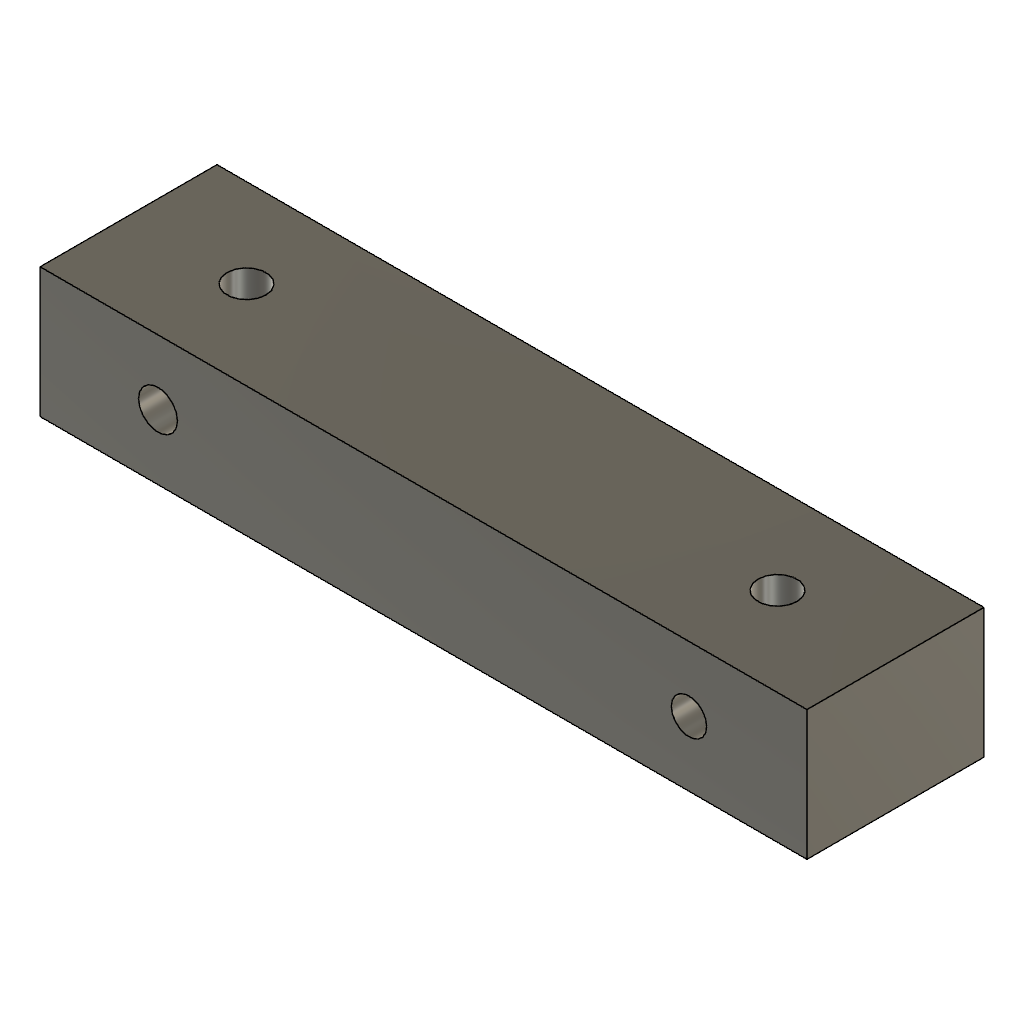
ecotwin_final (Autodesk Fusion 360 archive; units mm, degrees)
design "loadcell"
part number: 2026-10-23-00-33-52-910
Autodesk Fusion 360 part; units mm, degrees
sketch "Sketch1" plane through (0, 0, 0) normal (0, 0, 1) x (1, 0, 0)
  line L0 (0, 0) -> (130, 0)
  line L1 (130, 0) -> (130, 30)
  line L2 (130, 30) -> (0, 30)
  line L3 (0, 30) -> (0, 0)
  dimension "d1" = 130
  dimension "d2" = 30
  constraint horizontal L0
  constraint vertical L1
  constraint horizontal L2
  constraint vertical L3
  constraint coincident L0.start L3.end
  measures "d1" distance of L0.start L0.end
  measures "d2" distance of L0.start L2.end
extrude "Extrude1" add sketch "Sketch1" along normal blind 22
sketch "Sketch2" plane through (0, 0, 22) normal (0, 0, 1) x (-1, 0, 0)
  line L0 (0, -30) -> (0, 0)
  line L1 (0, 0) -> (-130, 0)
  line L2 (-130, 0) -> (-130, -30)
  line L3 (-130, -30) -> (0, -30)
  circle A0 centre (-110, -15) radius 3.3
  circle A1 centre (-20, -15) radius 3.3
  dimension "d7" = 6.6
  dimension "d8" = 6.6
  dimension "d11" = 15
  dimension "d12" = 20
  dimension "d13" = 20
  dimension "d15" = 15
  measures "d7" diameter of A0
  measures "d8" diameter of A1
  measures "d11" distance of L1 A1.centre
  measures "d12" distance of L0 A1.centre
  measures "d13" distance of L2 A0.centre
  measures "d15" distance of L1 A0.centre
sketch "Sketch3" plane through (0, 30, 0) normal (0, 1, 0) x (-1, 0, 0)
  line L0 (-130, 0) -> (0, 0)
  line L1 (0, 0) -> (0, 22)
  line L2 (0, 22) -> (-130, 22)
  line L3 (-130, 22) -> (-130, 0)
  circle A0 centre (-20, 11) radius 3.3
  circle A1 centre (-110, 11) radius 3
  dimension "d17" = 6.6
  dimension "d18" = 6
  dimension "d19" = 20
  dimension "d20" = 11
  dimension "d21" = 11
  dimension "d22" = 20
  measures "d17" diameter of A0
  measures "d18" diameter of A1
  measures "d19" distance of L1 A0.centre
  measures "d20" distance of L0 A0.centre
  measures "d21" distance of L0 A1.centre
  measures "d22" distance of L3 A1.centre
extrude "Extrude2" cut sketch "Sketch2" against normal blind 3 contours A0 | A1
extrude "Extrude3" cut sketch "Sketch3" against normal blind 3 contours A0 | A1
extrude "Extrude4" cut 2 faces at (19.1719, 16.8039, 19) (110.8064, 14.2518, 19) along direction (0, 0, -1) through all
extrude "Extrude5" cut 2 faces at (19.2059, 27, 11.9121) (110.7442, 27, 11.5311) along direction (0, -1, 0) through all

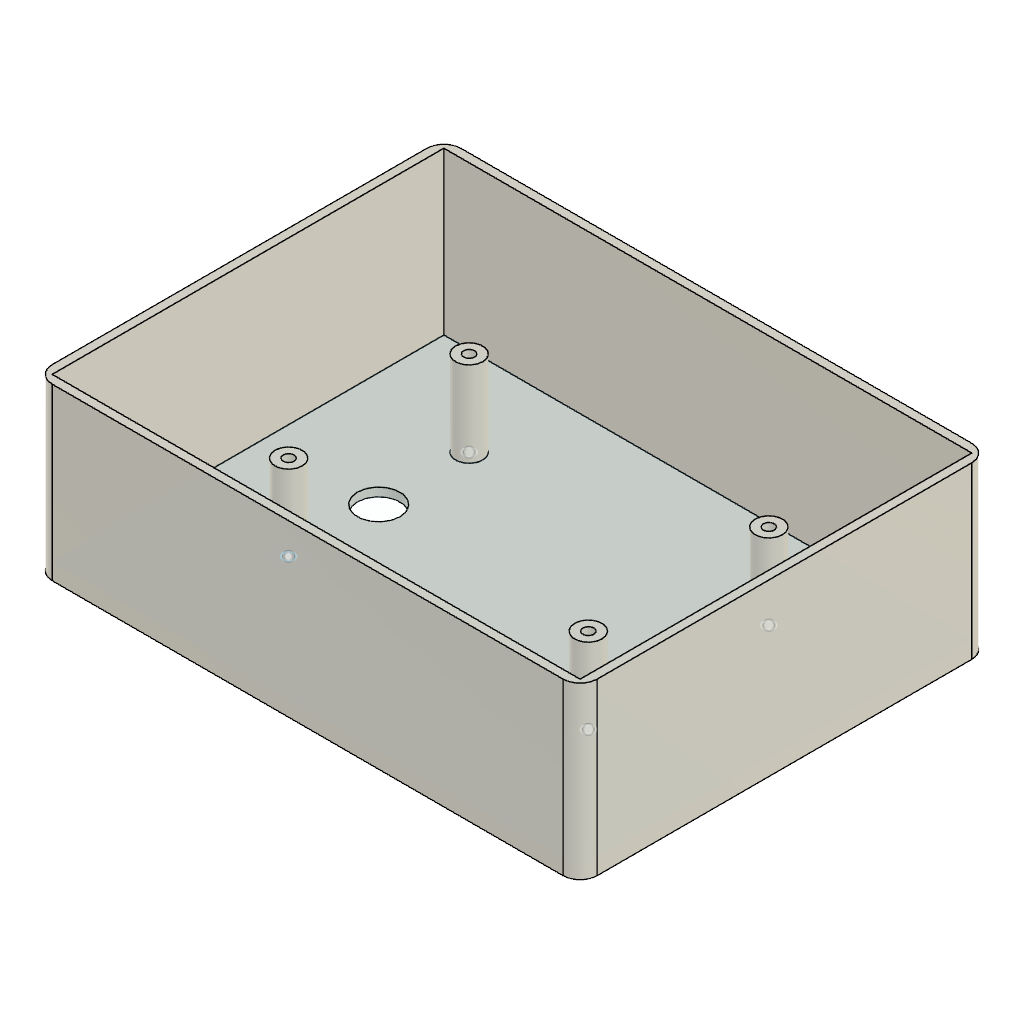
design "brain pod"
part number: 2026-10-24-10-44-46-187
Autodesk Fusion 360 part; units mm, degrees
sketch "Sketch1" plane through (0, 0, 0) normal (0, 0, 1) x (1, 0, 0)
  line L0 (0, 0) -> (160, 0)
  line L1 (160, 0) -> (160, 120)
  line L2 (160, 120) -> (0, 120)
  line L3 (0, 120) -> (0, 0)
  dimension "d1" = 160
  dimension "d2" = 120
  constraint horizontal L0
  constraint vertical L1
  constraint horizontal L2
  constraint vertical L3
  constraint coincident L0.start L3.end
  measures "d1" distance of L0.start L0.end
  measures "d2" distance of L0.start L2.end
extrude "Extrude1" add sketch "Sketch1" along normal blind 50
shell "Shell1" thickness 2.5 removed faces 1 at (53.3333, 80, 50)
fillet "Fillet1" radius 5 4 edges at (0, 0, 25) (160, 120, 25) (160, 0, 25) (0, 120, 25)
sketch "Sketch2" plane through (0, 0, 2.5) normal (0, 0, 1) x (-1, 0, 0)
  line L0 (-2.5, -117.5) -> (-2.5, -2.5)
  line L1 (-2.5, -2.5) -> (-157.5, -2.5)
  line L2 (-157.5, -2.5) -> (-157.5, -117.5)
  line L3 (-157.5, -117.5) -> (-2.5, -117.5)
  circle A0 centre (-36, -91.4107) radius 4
  circle A1 centre (-124, -91.4107) radius 4
  circle A2 centre (-36, -38.4107) radius 4
  circle A3 centre (-124, -38.4107) radius 4
  line L4 (-80, -120) -> (-80, -60)
  line L5 (-0.0841, -64.9107) -> (-80.0841, -64.9107)
  dimension "d8" = 8
  dimension "d9" = 8
  dimension "d10" = 8
  dimension "d11" = 8
  dimension "d12" = 60
  dimension "d13" = 80
  dimension "d14" = 44
  dimension "d15" = 44
  dimension "d16" = 44
  dimension "d17" = 44
  dimension "d18" = 26.5
  dimension "d19" = 26.5
  dimension "d20" = 26.5
  dimension "d21" = 26.5
  constraint perpendicular L3 L4
  constraint perpendicular L0 L5
  measures "d8" diameter of A0
  measures "d9" diameter of A1
  measures "d10" diameter of A2
  measures "d11" diameter of A3
  measures "d12" distance of L4.start L4.end
  measures "d13" distance of L5.start L5.end
  measures "d14" distance of A0.centre L4
  measures "d15" distance of A1.centre L4
  measures "d16" distance of A2.centre L4
  measures "d17" distance of A3.centre L4
  measures "d18" distance of A0.centre L5
  measures "d19" distance of A1.centre L5
  measures "d20" distance of A2.centre L5
  measures "d21" distance of A3.centre L5
extrude "Extrude2" add sketch "Sketch2" along normal blind 25 contours A0 | A1 | A2 | A3
sketch "Sketch3" plane through (0, 0, 2.5) normal (0, 0, 1) x (-1, 0, 0)
  circle A0 centre (-36, -38.4107) radius 4
  circle A1 centre (-124, -38.4107) radius 4
  circle A2 centre (-36, -91.4107) radius 4
  circle A3 centre (-124, -91.4107) radius 4
  line L0 (-2.5, -117.5) -> (-2.5, -2.5)
  line L1 (-2.5, -2.5) -> (-157.5, -2.5)
  line L2 (-157.5, -2.5) -> (-157.5, -117.5)
  line L3 (-157.5, -117.5) -> (-2.5, -117.5)
  circle A4 centre (-36, -91.4107) radius 1.6
  circle A5 centre (-124, -91.4107) radius 1.6
  circle A6 centre (-124, -38.4107) radius 1.6
  circle A7 centre (-36, -38.4107) radius 1.6
  dimension "d24" = 3.2
  dimension "d25" = 3.2
  dimension "d26" = 3.2
  dimension "d27" = 3.2
  constraint concentric A2 A4
  constraint concentric A3 A5
  constraint concentric A1 A6
  constraint concentric A0 A7
  measures "d24" diameter of A4
  measures "d25" diameter of A5
  measures "d26" diameter of A6
  measures "d27" diameter of A7
sketch "Sketch4" plane through (0, 0, 2.5) normal (0, 0, 1) x (-1, 0, 0)
  circle A0 centre (-35.9649, -38.3568) radius 1.6
  dimension "d28" = 3.2
  measures "d28" diameter of A0
sketch "Sketch5" plane through (0, 0, 27.5) normal (0, 0, 1) x (-1, 0, 0)
  circle A0 centre (-36, -38.4107) radius 4
  circle A1 centre (-36, -38.4107) radius 1.6
  dimension "d29" = 3.2
  constraint concentric A0 A1
  measures "d29" diameter of A1
extrude "Extrude3" cut sketch "Sketch5" against normal through all contours A1
sketch "Sketch6" plane through (0, 0, 27.5) normal (0, 0, 1) x (-1, 0, 0)
  circle A0 centre (-36, -91.4107) radius 4
  circle A1 centre (-36, -91.4107) radius 1.6
  dimension "d31" = 3.2
  constraint concentric A0 A1
  measures "d31" diameter of A1
sketch "Sketch7" plane through (0, 0, 27.5) normal (0, 0, 1) x (-1, 0, 0)
  circle A0 centre (-124, -91.4107) radius 4
  circle A1 centre (-124, -91.4107) radius 1.6
  dimension "d32" = 3.2
  constraint concentric A0 A1
  measures "d32" diameter of A1
sketch "Sketch8" plane through (0, 0, 27.5) normal (0, 0, 1) x (-1, 0, 0)
  circle A0 centre (-124, -38.4107) radius 4
  circle A1 centre (-124, -38.4107) radius 1.6
  dimension "d33" = 3.2
  constraint concentric A0 A1
  measures "d33" diameter of A1
extrude "Extrude4" cut sketch "Sketch8" sketch "Sketch7" sketch "Sketch6" against normal through all contours A1 of sketch 2 contours A1 of sketch 3 contours A1
sketch "Sketch9" plane through (0, 0, 0) normal (0, 0, -1) x (1, 0, 0)
  circle A0 centre (124, -91.4107) radius 1.6
  circle A1 centre (124, -38.4107) radius 1.6
  circle A2 centre (36, -91.4107) radius 1.6
  circle A3 centre (36, -38.4107) radius 1.6
  arc A4 (0, -115) -> (5, -120) centre (5, -115) ccw
  line L0 (5, -120) -> (155, -120)
  arc A5 (155, -120) -> (160, -115) centre (155, -115) ccw
  line L1 (160, -115) -> (160, -5)
  arc A6 (160, -5) -> (155, 0) centre (155, -5) ccw
  line L2 (155, 0) -> (5, 0)
  arc A7 (5, 0) -> (0, -5) centre (5, -5) ccw
  line L3 (0, -5) -> (0, -115)
  circle A8 centre (80, -38.411) radius 6.25
  circle A9 centre (36, -64.8568) radius 6.25
  circle A10 centre (124, -64.9107) radius 6.25
  circle A11 centre (36, -38.4107) radius 4
  circle A12 centre (36, -91.4107) radius 1.6
  point P0 (36, -38.4107)
  point P1 (35.9649, -38.3568)
  point P2 (124, -38.4107)
  dimension "d35" = 12.5
  dimension "d36" = 12.5
  dimension "d37" = 12.5
  dimension "d38" = 44
  dimension "d39" = 38.4107
  dimension "d40" = 38.411
  dimension "d41" = 36
  dimension "d42" = 26.5
  dimension "d43" = 53
  dimension "d44" = 36
  dimension "d45" = 26.5
  measures "d35" diameter of A8
  measures "d36" diameter of A9
  measures "d37" diameter of A10
  measures "d38" horizontal distance of A8.centre P0
  measures "d39" distance of L2 P0
  measures "d40" distance of L2 A8.centre
  measures "d41" distance of L3 A9.centre
  measures "d42" distance of A9.centre P1
  measures "d43" distance of P0 A2.centre
  measures "d44" distance of L1 A10.centre
  measures "d45" distance of A10.centre P2
extrude "Extrude5" cut sketch "Sketch9" against normal through all contours A8 | A9 | A10

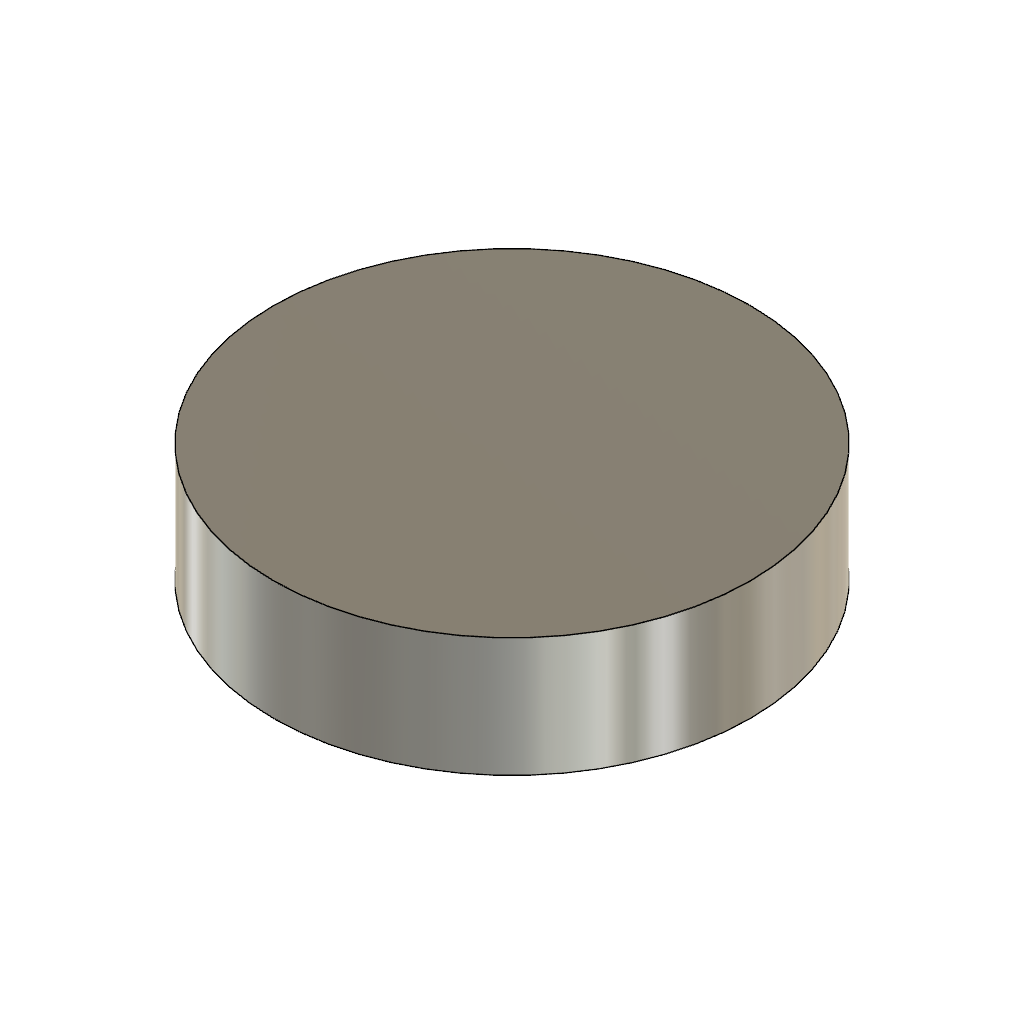
design "spacer"
part number: 2026-10-23-11-01-43-510
Autodesk Fusion 360 part; units mm, degrees
sketch "Sketch1" plane through (0, 0, 0) normal (0, 0, 1) x (1, 0, 0)
  circle A0 centre (0, 0) radius 6
  dimension "d1" = 12
  constraint coincident A0.centre origin
  measures "d1" diameter of A0
extrude "Extrude1" add sketch "Sketch1" along normal blind 3

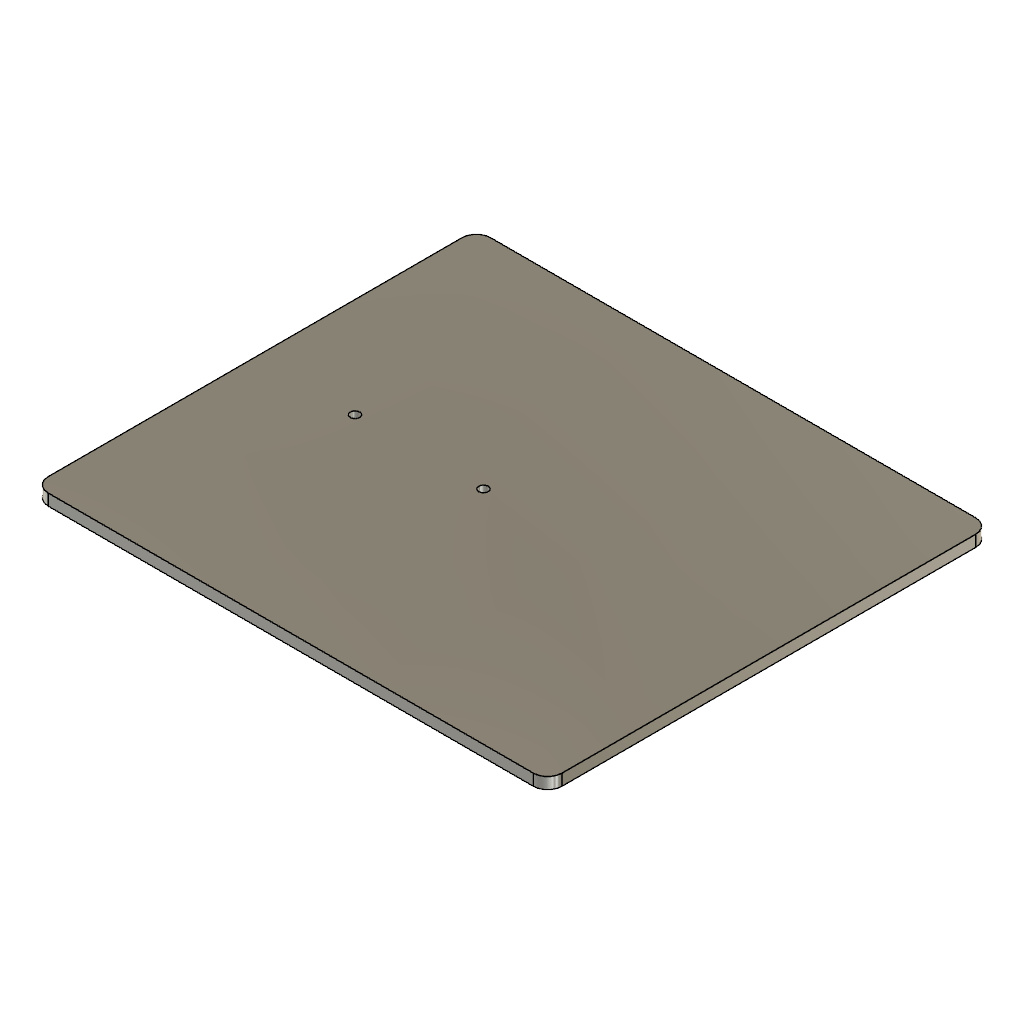
design "platform"
part number: 2026-10-23-11-06-21-150
Autodesk Fusion 360 part; units mm, degrees
sketch "Sketch1" plane through (0, 0, 0) normal (0, 0, 1) x (1, 0, 0)
  line L0 (0, 0) -> (360, 0)
  line L1 (360, 0) -> (360, 310)
  line L2 (360, 310) -> (0, 310)
  line L3 (0, 310) -> (0, 0)
  dimension "d1" = 360
  dimension "d2" = 310
  constraint horizontal L0
  constraint vertical L1
  constraint horizontal L2
  constraint vertical L3
  constraint coincident L0.start L3.end
  measures "d1" distance of L0.start L0.end
  measures "d2" distance of L0.start L2.end
extrude "Extrude1" add sketch "Sketch1" along normal blind 8
fillet "Fillet1" radius 10 4 edges at (360, 0, 4) (0, 0, 4) (0, 310, 4) (360, 310, 4)
sketch "Sketch2" plane through (0, 0, 8) normal (0, 0, 1) x (-1, 0, 0)
  arc A0 (-360, -300) -> (-350, -310) centre (-350, -300) ccw
  line L0 (-350, -310) -> (-10, -310)
  arc A1 (-10, -310) -> (0, -300) centre (-10, -300) ccw
  line L1 (0, -300) -> (0, -10)
  arc A2 (0, -10) -> (-10, 0) centre (-10, -10) ccw
  line L2 (-10, 0) -> (-350, 0)
  arc A3 (-350, 0) -> (-360, -10) centre (-350, -10) ccw
  line L3 (-360, -10) -> (-360, -300)
  circle A4 centre (-165, -145) radius 3.3
  circle A5 centre (-165, -165) radius 3.3
  dimension "d7" = 360
  dimension "d8" = 310
  dimension "d9" = 6.6
  dimension "d10" = 6.6
  dimension "d11" = 165
  dimension "d12" = 145
  dimension "d13" = 165
  dimension "d14" = 165
  measures "d7" distance of L1 L3
  measures "d8" distance of L0 L2
  measures "d9" diameter of A4
  measures "d10" diameter of A5
  measures "d11" distance of L1 A4.centre
  measures "d12" distance of L2 A4.centre
  measures "d13" distance of L1 A5.centre
  measures "d14" distance of L2 A5.centre
sketch "Sketch3" plane through (0, 0, 8) normal (0, 0, 1) x (-1, 0, 0)
  arc A0 (-360, -300) -> (-350, -310) centre (-350, -300) ccw
  line L0 (-350, -310) -> (-10, -310)
  arc A1 (-10, -310) -> (0, -300) centre (-10, -300) ccw
  line L1 (0, -300) -> (0, -10)
  arc A2 (0, -10) -> (-10, 0) centre (-10, -10) ccw
  line L2 (-10, 0) -> (-350, 0)
  arc A3 (-350, 0) -> (-360, -10) centre (-350, -10) ccw
  line L3 (-360, -10) -> (-360, -300)
  circle A4 centre (-70, -155) radius 3.3
  circle A5 centre (-160, -155) radius 3.3
  dimension "d16" = 6.6
  dimension "d17" = 6.6
  dimension "d18" = 155
  dimension "d19" = 155
  dimension "d20" = 70
  dimension "d21" = 160
  measures "d16" diameter of A4
  measures "d17" diameter of A5
  measures "d18" distance of L2 A4.centre
  measures "d19" distance of L2 A5.centre
  measures "d20" distance of L1 A4.centre
  measures "d21" distance of L1 A5.centre
extrude "Extrude3" cut sketch "Sketch3" against normal through all contours A4 | A5

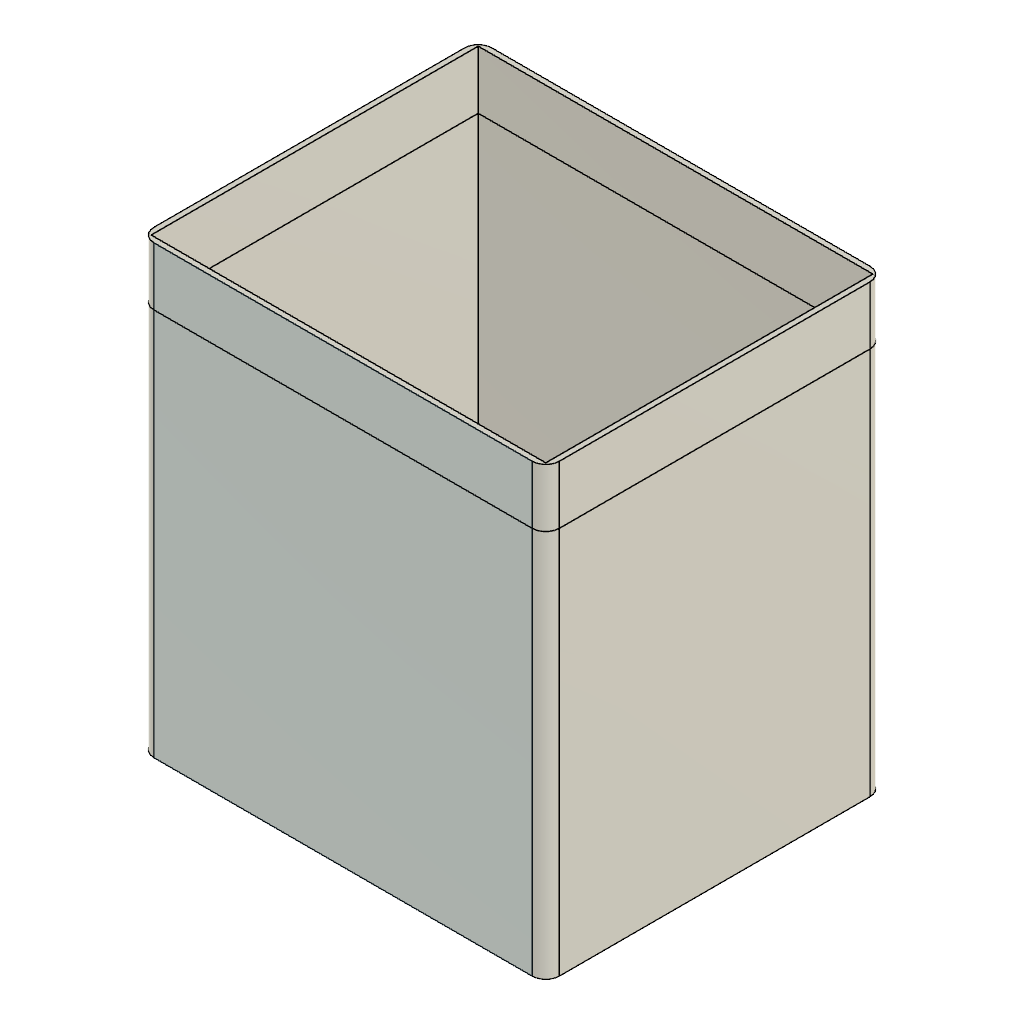
design "tank"
part number: 2026-10-23-13-51-54-774
Autodesk Fusion 360 part; units mm, degrees
sketch "Sketch1" plane through (0, 0, 0) normal (0, 0, 1) x (1, 0, 0)
  line L0 (0, 0) -> (300, 0)
  line L1 (300, 0) -> (300, 250)
  line L2 (300, 250) -> (0, 250)
  line L3 (0, 250) -> (0, 0)
  dimension "d1" = 300
  dimension "d2" = 250
  constraint horizontal L0
  constraint vertical L1
  constraint horizontal L2
  constraint vertical L3
  constraint coincident L0.start L3.end
  measures "d1" distance of L0.start L0.end
  measures "d2" distance of L0.start L2.end
extrude "Extrude1" add sketch "Sketch1" along normal blind 330 makes body 1
shell "Shell1" thickness 4 removed faces 1 at (100, 166.6667, 330) on bodies 1
fillet "Fillet1" radius 10 4 edges at (0, 0, 165) (300, 0, 165) (300, 250, 165) (0, 250, 165) on bodies 1
sketch "Sketch2" plane through (0, 0, 0) normal (0, -1, 0) x (1, 0, 0)
  line L0 (290, 0) -> (290, 330)
  line L1 (290, 330) -> (10, 330)
  line L2 (10, 330) -> (10, 0)
  line L3 (10, 0) -> (290, 0)
sketch "Sketch3" plane through (296, 0, 0) normal (-1, 0, 0) x (0, -1, 0)
  line L0 (-246, 4) -> (-4, 4)
  line L1 (-4, 4) -> (-4, 330)
  line L2 (-4, 330) -> (-246, 330)
  line L3 (-246, 330) -> (-246, 4)
  line L4 (-246, 287) -> (-4, 287)
  dimension "d8" = 283
  constraint coincident L3 L4.start
  constraint coincident L1 L4.end
  constraint perpendicular L1 L4
  measures "d8" distance of L0 L4
split_face "SplitFace1" 1 faces at (296, 84.6667, 221.3333) by curves path "Sketch3" along L4 on bodies 1
sketch "Sketch4" plane through (0, 4, 0) normal (0, 1, 0) x (-1, 0, 0)
  line L0 (-296, 4) -> (-4, 4)
  line L1 (-4, 4) -> (-4, 330)
  line L2 (-4, 330) -> (-296, 330)
  line L3 (-296, 330) -> (-296, 287)
  line L4 (-296, 287) -> (-296, 4)
  line L5 (-296, 287) -> (-8.9892, 287)
  dimension "d9" = 283
  constraint coincident L4 L3.end
  constraint perpendicular L4 L5
  measures "d9" distance of L0 L5
split_face "SplitFace2" 1 faces at (196.6667, 250, 220) by curves path "Sketch4" along L5 on bodies 1
sketch "Sketch5" plane through (0, 4, 0) normal (0, 1, 0) x (-1, 0, 0)
  line L0 (-296, 4) -> (-4, 4)
  line L1 (-4, 4) -> (-4, 330)
  line L2 (-4, 330) -> (-296, 330)
  line L3 (-296, 330) -> (-296, 287)
  line L4 (-296, 287) -> (-296, 4)
  line L5 (-296, 287) -> (-4, 287)
  dimension "d10" = 283
  constraint coincident L4 L3.end
  constraint coincident L1 L5.end
  constraint perpendicular L1 L5
  measures "d10" distance of L0 L5
split "Split1" by curves path "Sketch5" along L5 bodies 1 makes body 2 at (101.3333, 4, 98.3333)

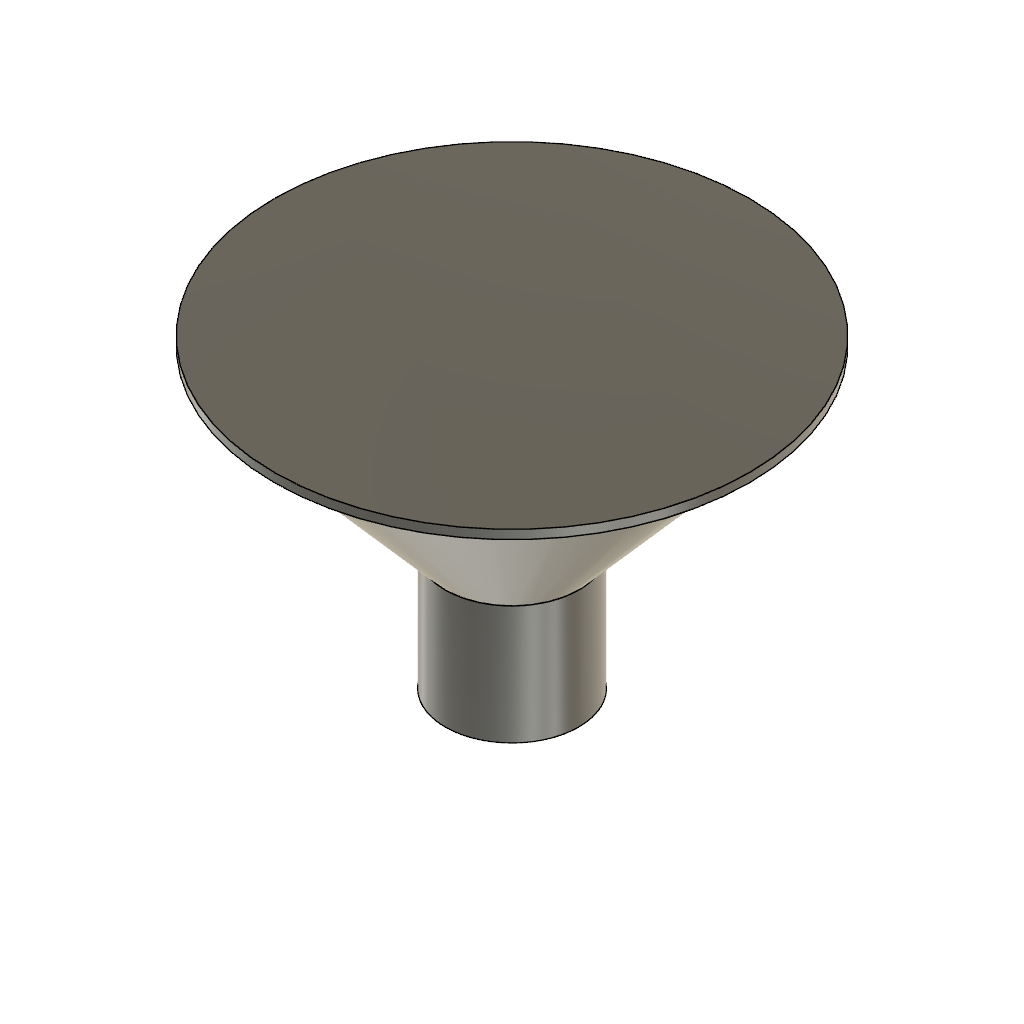
design "funnel2"
part number: 2026-10-23-16-01-08-975
Autodesk Fusion 360 part; units mm, degrees
sketch "Sketch1" plane through (0, 0, 0) normal (0, 1, 0) x (1, 0, 0)
  line L0 (0, 0) -> (22.5, 0)
  line L1 (0, 0) -> (0, -60)
  line L2 (0, -60) -> (75, -60)
  line L3 (75, -60) -> (22.5, 0)
  dimension "d1" = 22.5
  dimension "d2" = 60
  dimension "d3" = 75
  constraint coincident L0.start L1.start
  constraint horizontal L0
  constraint perpendicular L0 L1
  constraint perpendicular L1 L2
  measures "d1" distance of L0.start L0.end
  measures "d2" distance of L0.start L1.end
  measures "d3" distance of L1.end L2.end
revolve "Revolve1" add sketch "Sketch1" angle 360 about axis through (0, 0, 0) along (0, 0, 1) makes body 1
shell "Shell1" thickness 2 removed faces 1 at (1.3651, 18.216, 60) on bodies 1
sketch "Sketch2" plane through (0, 0, 0) normal (0, 0, -1) x (1, 0, 0)
  circle A0 centre (0, 0) radius 22.5
  circle A1 centre (0, 0) radius 22.5
  dimension "d6" = 45
  constraint coincident A0.centre A1.centre
  measures "d6" diameter of A1
extrude "Extrude1" cut sketch "Sketch2" against normal through all bodies 1
sketch "Sketch3" plane through (0, 0, 0) normal (0, 0, 1) x (1, 0, 0)
  circle A0 centre (0, 0) radius 22.5
  dimension "d8" = 45
  constraint coincident A0.centre origin
  measures "d8" diameter of A0
extrude "Extrude2" add sketch "Sketch3" against normal blind 40 thin wall 1 on the right separate body open curves A0 makes body 2
sketch "Sketch4" plane through (0, 0, 0) normal (0, 0, 1) x (1, 0, 0)
  circle A0 centre (-200, 0) radius 80
  dimension "d12" = 160
  measures "d12" diameter of A0
extrude "Extrude3" add sketch "Sketch4" along normal blind 3 separate body makes body 3
move_body "Align1" bodies 3 to x (1, 0, 0) y (0, 1, 0) z (0, 0, 1) at (0, 0, -43)
move_body "Align2" bodies 3 to x (1, 0, 0) y (0, 1, 0) z (0, 0, 1) at (200, 0, 100)
move_body "Move1" bodies 3 to x (1, 0, 0) y (0, 1, 0) z (0, 0, 1) at (0, 0, 20)
move_body "Align3" bodies 3 to x (1, 0, 0) y (0, 1, 0) z (0, 0, 1) at (0, 0, -17)

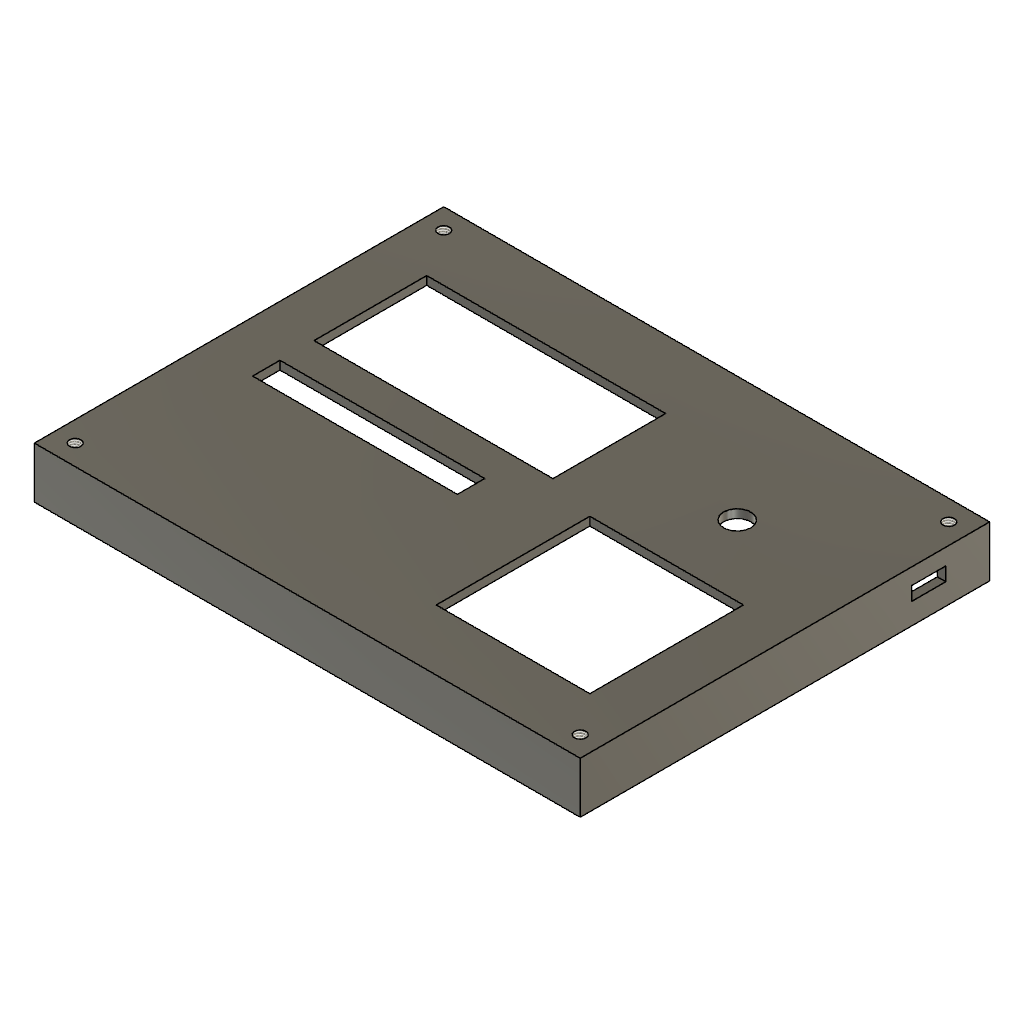
design "pod lid"
part number: 2026-10-24-11-16-07-348
Autodesk Fusion 360 part; units mm, degrees
sketch "Sketch1" plane through (0, 0, 0) normal (0, 0, 1) x (1, 0, 0)
  line L0 (0, 0) -> (160, 0)
  line L1 (160, 0) -> (160, -120)
  line L2 (160, -120) -> (0, -120)
  line L3 (0, -120) -> (0, 0)
  dimension "d1" = 160
  dimension "d2" = 120
  constraint horizontal L0
  constraint vertical L1
  constraint horizontal L2
  constraint vertical L3
  constraint coincident L0.start L3.end
  measures "d1" distance of L0.start L0.end
  measures "d2" distance of L0.start L2.end
extrude "Extrude1" add sketch "Sketch1" along normal blind 15
shell "Shell1" thickness 2.5 removed faces 1 at (53.3333, -40, 0)
sketch "Sketch2" plane through (0, 0, 0) normal (0, 0, -1) x (1, 0, 0)
  line L0 (2.5, 2.5) -> (2.5, 117.5)
  line L1 (2.5, 117.5) -> (157.5, 117.5)
  line L2 (157.5, 117.5) -> (157.5, 2.5)
  line L3 (157.5, 2.5) -> (2.5, 2.5)
  line L4 (160, 120) -> (0, 120)
  line L5 (0, 120) -> (0, 0)
  line L6 (0, 0) -> (160, 0)
  line L7 (160, 0) -> (160, 120)
  line L8 (157.5, 2.5) -> (2.5, 2.5)
  line L9 (2.5, 2.5) -> (2.5, 117.5)
  line L10 (2.5, 117.5) -> (157.5, 117.5)
  line L11 (157.5, 117.5) -> (157.5, 2.5)
  line L12 (157.5, 2.5) -> (2.5, 117.5) construction
  line L13 (2.5, 2.5) -> (157.5, 117.5) construction
  line L14 (158.5, 118.5) -> (1.5, 118.5)
  line L15 (1.5, 118.5) -> (1.5, 1.5)
  line L16 (1.5, 1.5) -> (158.5, 1.5)
  line L17 (158.5, 1.5) -> (158.5, 118.5)
  line L18 (158.5, 118.5) -> (1.5, 1.5) construction
  line L19 (1.5, 118.5) -> (158.5, 1.5) construction
  point P0 (80, 60)
  point P1 (80, 60)
  dimension "d6" = 157
  dimension "d7" = 117
  constraint horizontal L8
  constraint perpendicular L8 L9
  constraint parallel L8 L10
  constraint parallel L9 L11
  constraint coincident L12 P1
  constraint coincident L13 P1
  constraint coincident L2.end L3.start
  constraint horizontal L14
  constraint perpendicular L14 L15
  constraint parallel L14 L16
  constraint parallel L15 L17
  constraint coincident L18 P1
  constraint coincident L19 P1
  constraint coincident P1 P0
  measures "d6" distance of L15.end L16.end
  measures "d7" distance of L14.end L15.end
extrude "Extrude2" cut sketch "Sketch2" against normal blind 2 contours L14 L15 L16 L17
sketch "Sketch3" plane through (0, 0, 15) normal (0, 0, 1) x (-1, 0, 0)
  line L0 (0, 120) -> (-160, 120)
  line L1 (-160, 120) -> (-160, 0)
  line L2 (-160, 0) -> (0, 0)
  line L3 (0, 0) -> (0, 120)
  circle A0 centre (-6, 6) radius 2
  circle A1 centre (-154, 6) radius 2
  circle A2 centre (-6, 114) radius 2
  circle A3 centre (-154, 114) radius 2
  dimension "d10" = 4
  dimension "d11" = 4
  dimension "d12" = 4
  dimension "d13" = 4
  dimension "d14" = 6
  dimension "d15" = 6
  dimension "d16" = 6
  dimension "d17" = 6
  dimension "d18" = 6
  dimension "d19" = 6
  dimension "d20" = 6
  dimension "d21" = 6
  measures "d10" diameter of A0
  measures "d11" diameter of A1
  measures "d12" diameter of A2
  measures "d13" diameter of A3
  measures "d14" distance of L3 A0.centre
  measures "d15" distance of L2 A0.centre
  measures "d16" distance of L2 A1.centre
  measures "d17" distance of L1 A1.centre
  measures "d18" distance of L3 A2.centre
  measures "d19" distance of L0 A2.centre
  measures "d20" distance of L1 A3.centre
  measures "d21" distance of L0 A3.centre
extrude "Extrude3" cut sketch "Sketch3" against normal through all contours A0 | A1 | A2 | A3
thread "Thread1" "ISO Metric profile 4.0 M4x0.7 M4x0.7 6H" major diameter 4.1095 minor diameter 3.332 pitch 0.7 angle 60 resizes the face on face at (4.0099, -5.8009, 14.1667)
thread "Thread2" "ISO Metric profile 4.0 M4x0.7 M4x0.7 6H" major diameter 4.1095 minor diameter 3.332 pitch 0.7 angle 60 resizes the face on face at (152.8325, -7.6239, 14.1667)
thread "Thread3" "ISO Metric profile 4.0 M4x0.7 M4x0.7 6H" major diameter 4.1095 minor diameter 3.332 pitch 0.7 angle 60 resizes the face on face at (152.157, -114.7769, 13.3333)
thread "Thread4" "ISO Metric profile 4.0 M4x0.7 M4x0.7 6H" major diameter 4.1095 minor diameter 3.332 pitch 0.7 angle 60 resizes the face on face at (4.157, -114.7769, 13.3333)
sketch "Sketch4" plane through (0, 0, 15) normal (0, 0, 1) x (-1, 0, 0)
  circle A0 centre (-154, 6) radius 1.666
  circle A1 centre (-154, 114) radius 1.666
  circle A2 centre (-6, 6) radius 1.666
  circle A3 centre (-6, 114) radius 1.666
  line L0 (0, 120) -> (-160, 120)
  line L1 (-160, 120) -> (-160, 0)
  line L2 (-160, 0) -> (0, 0)
  line L3 (0, 0) -> (0, 120)
  line L4 (-15, 20) -> (-85, 20)
  line L5 (-85, 20) -> (-85, 53)
  line L6 (-85, 53) -> (-15, 53)
  line L7 (-15, 53) -> (-15, 20)
  line L8 (-15, 63) -> (-75, 63)
  line L9 (-75, 63) -> (-75, 71)
  line L10 (-75, 71) -> (-15, 71)
  line L11 (-15, 71) -> (-15, 63)
  circle A4 centre (-122.5, 36.5) radius 4
  line L12 (-122.5, 36.5) -> (-122.5, 96.5)
  line L13 (-145, 102.1885) -> (-100, 102.1885)
  line L14 (-100, 102.1885) -> (-100, 57.1885)
  line L15 (-100, 57.1885) -> (-145, 57.1885)
  line L16 (-145, 57.1885) -> (-145, 102.1885)
  line L17 (-145, 102.1885) -> (-100, 57.1885) construction
  line L18 (-100, 102.1885) -> (-145, 57.1885) construction
  point P0 (-122.5, 79.6885)
  dimension "d31" = 70
  dimension "d32" = 33
  dimension "d33" = 20
  dimension "d34" = 15
  dimension "d35" = 60
  dimension "d36" = 8
  dimension "d37" = 15
  dimension "d38" = 10
  dimension "d39" = 8
  dimension "d40" = 36.5
  dimension "d41" = 37.5
  dimension "d42" = 60
  dimension "d43" = 45
  dimension "d44" = 45
  dimension "d45" = 43.1885
  dimension "d46" = 20.6885
  constraint horizontal L4
  constraint vertical L5
  constraint horizontal L6
  constraint vertical L7
  constraint horizontal L8
  constraint vertical L9
  constraint horizontal L10
  constraint vertical L11
  constraint coincident A4.centre L12.start
  constraint vertical L12
  constraint horizontal L13
  constraint perpendicular L13 L14
  constraint parallel L13 L15
  constraint parallel L14 L16
  constraint coincident L17 P0
  constraint coincident L18 P0
  constraint coincident L12 P0
  measures "d31" distance of L4.start L4.end
  measures "d32" distance of L4.start L6.end
  measures "d33" distance of L2 L4
  measures "d34" distance of L3 L7
  measures "d35" distance of L8.start L8.end
  measures "d36" distance of L8.start L10.end
  measures "d37" distance of L3 L10.end
  measures "d38" distance of L6 L8
  measures "d39" diameter of A4
  measures "d40" distance of L2 A4.centre
  measures "d41" distance of L5 A4.centre
  measures "d42" distance of A4.centre L12.end
  measures "d43" distance of L14.end L15.end
  measures "d44" distance of L13.end L14.end
  measures "d45" distance of A4.centre P0
  measures "d46" distance of A4.centre L15
extrude "Extrude4" cut sketch "Sketch4" against normal through all contours L4 L5 L6 L7 | L8 L9 L10 L11 | A4 | L13 L14 L15 L16
sketch "Sketch5" plane through (0, 0, 0) normal (-1, 0, 0) x (0, -1, 0)
  line L0 (0, 0) -> (120, 0)
  line L1 (120, 0) -> (120, 15)
  line L2 (120, 15) -> (0, 15)
  line L3 (0, 15) -> (0, 0)
  line L4 (12.8617, 10.24) -> (22.8617, 10.24)
  line L5 (22.8617, 10.24) -> (22.8617, 6.24)
  line L6 (22.8617, 6.24) -> (12.8617, 6.24)
  line L7 (12.8617, 6.24) -> (12.8617, 10.24)
  dimension "d48" = 10
  dimension "d49" = 4
  constraint horizontal L4
  constraint vertical L5
  constraint horizontal L6
  constraint vertical L7
  measures "d48" distance of L4.start L4.end
  measures "d49" distance of L4.start L6.end
extrude "Extrude5" cut sketch "Sketch5" against normal through all contours L4 L5 L6 L7

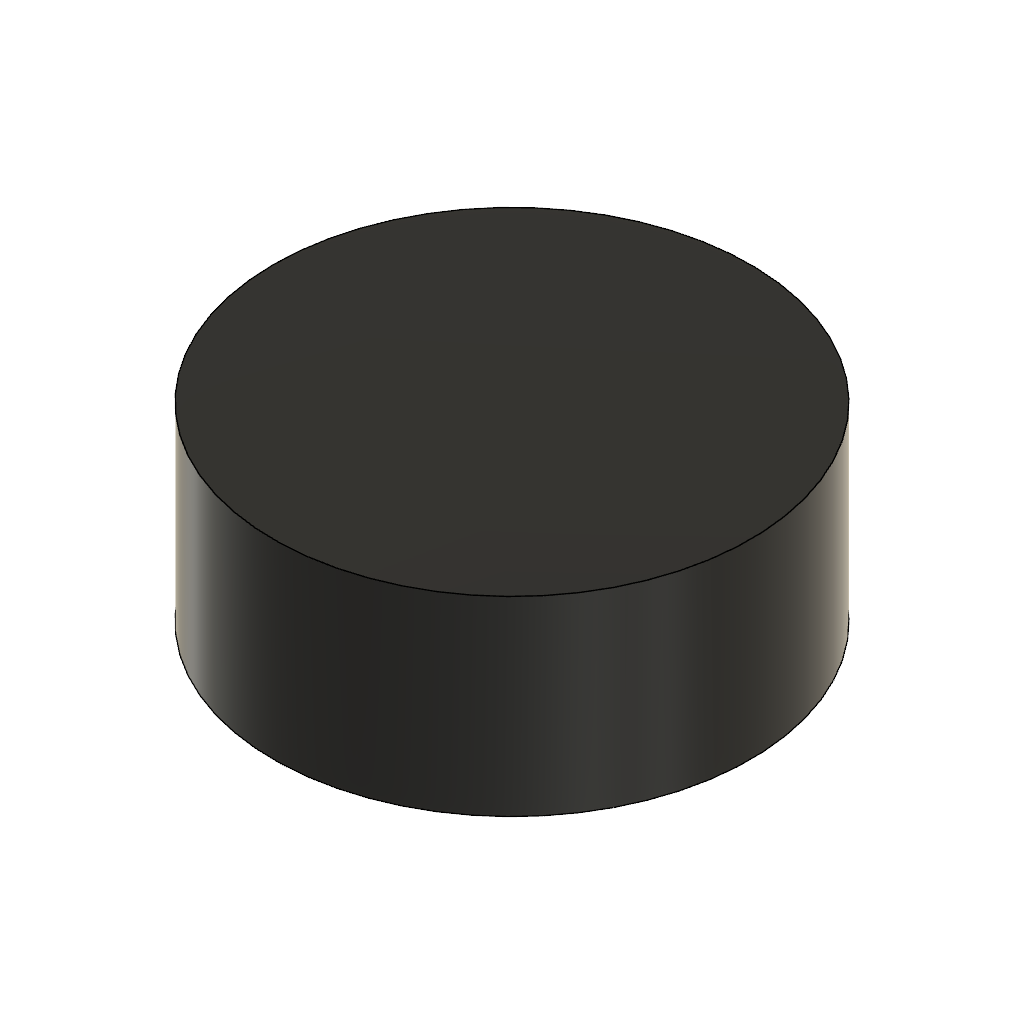
design "feet"
part number: 2026-10-23-10-13-56-642
Autodesk Fusion 360 part; units mm, degrees
sketch "Sketch1" plane through (0, 0, 0) normal (0, 0, 1) x (1, 0, 0)
  circle A0 centre (0, 0) radius 15
  dimension "d1" = 30
  constraint coincident A0.centre origin
  measures "d1" diameter of A0
extrude "Extrude1" add sketch "Sketch1" along normal blind 12

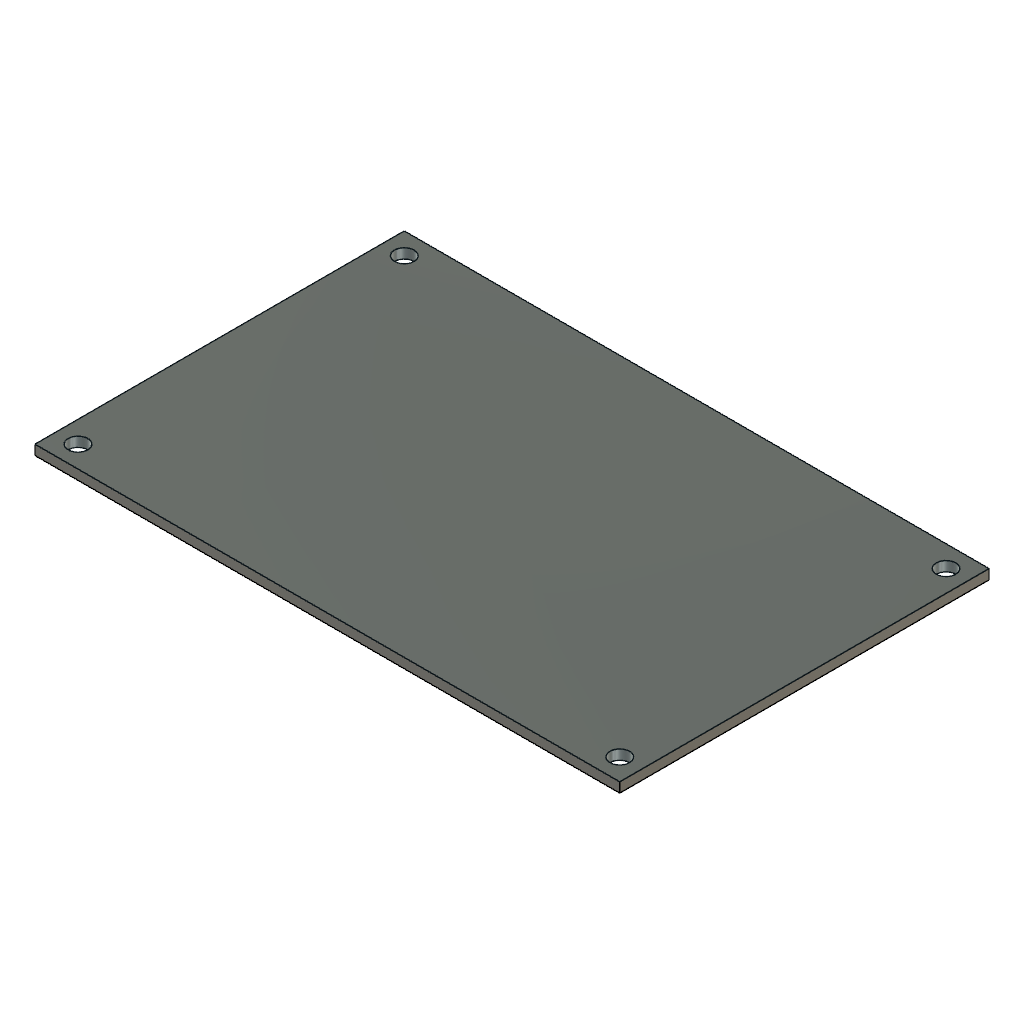
design "pcb"
part number: 2026-10-24-12-04-29-356
Autodesk Fusion 360 part; units mm, degrees
sketch "Sketch1" plane through (0, 0, 0) normal (0, 0, 1) x (1, 0, 0)
  line L0 (0, 0) -> (95, 0)
  line L1 (95, 0) -> (95, 60)
  line L2 (95, 60) -> (0, 60)
  line L3 (0, 60) -> (0, 0)
  dimension "d1" = 95
  dimension "d2" = 60
  constraint horizontal L0
  constraint vertical L1
  constraint horizontal L2
  constraint vertical L3
  constraint coincident L0.start L3.end
  measures "d1" distance of L0.start L0.end
  measures "d2" distance of L0.start L2.end
extrude "Extrude1" add sketch "Sketch1" along normal blind 1.6
sketch "Sketch2" plane through (0, 0, 1.6) normal (0, 0, 1) x (-1, 0, 0)
  line L0 (0, -60) -> (0, 0)
  line L1 (0, 0) -> (-95, 0)
  line L2 (-95, 0) -> (-95, -60)
  line L3 (-95, -60) -> (0, -60)
  circle A0 centre (-3.5, -56.5) radius 1.6
  circle A1 centre (-91.5, -56.5) radius 1.6
  circle A2 centre (-3.5, -3.5) radius 1.6
  circle A3 centre (-91.5, -3.5) radius 1.6
  dimension "d5" = 3.2
  dimension "d6" = 3.2
  dimension "d7" = 3.2
  dimension "d8" = 3.2
  dimension "d9" = 3.5
  dimension "d10" = 3.5
  dimension "d11" = 3.5
  dimension "d12" = 3.5
  dimension "d13" = 3.5
  dimension "d14" = 3.5
  dimension "d15" = 3.5
  dimension "d16" = 3.5
  dimension "d17" = 60
  dimension "d18" = 95
  measures "d5" diameter of A0
  measures "d6" diameter of A1
  measures "d7" diameter of A2
  measures "d8" diameter of A3
  measures "d9" distance of L0 A0.centre
  measures "d10" distance of L0 A2.centre
  measures "d11" distance of L3 A0.centre
  measures "d12" distance of L1 A2.centre
  measures "d13" distance of L3 A1.centre
  measures "d14" distance of L2 A1.centre
  measures "d15" distance of L2 A3.centre
  measures "d16" distance of L1 A3.centre
  measures "d17" distance of L1 L3
  measures "d18" distance of L0 L2
extrude "Extrude2" cut sketch "Sketch2" against normal through all contours A0 | A1 | A2 | A3
sketch "Sketch3" plane through (0, 0, 1.6) normal (0, 0, 1) x (-1, 0, 0)
  circle A0 centre (-91.5, -3.5) radius 1.6
  circle A1 centre (-3.5, -3.5) radius 1.6
  circle A2 centre (-91.5, -56.5) radius 1.6
  circle A3 centre (-3.5, -56.5) radius 1.6
  line L0 (0, -60) -> (0, 0)
  line L1 (0, 0) -> (-95, 0)
  line L2 (-95, 0) -> (-95, -60)
  line L3 (-95, -60) -> (0, -60)
  dimension "d20" = 88
  dimension "d21" = 53
  measures "d20" distance of A2.centre A3.centre
  measures "d21" distance of A1.centre A3.centre

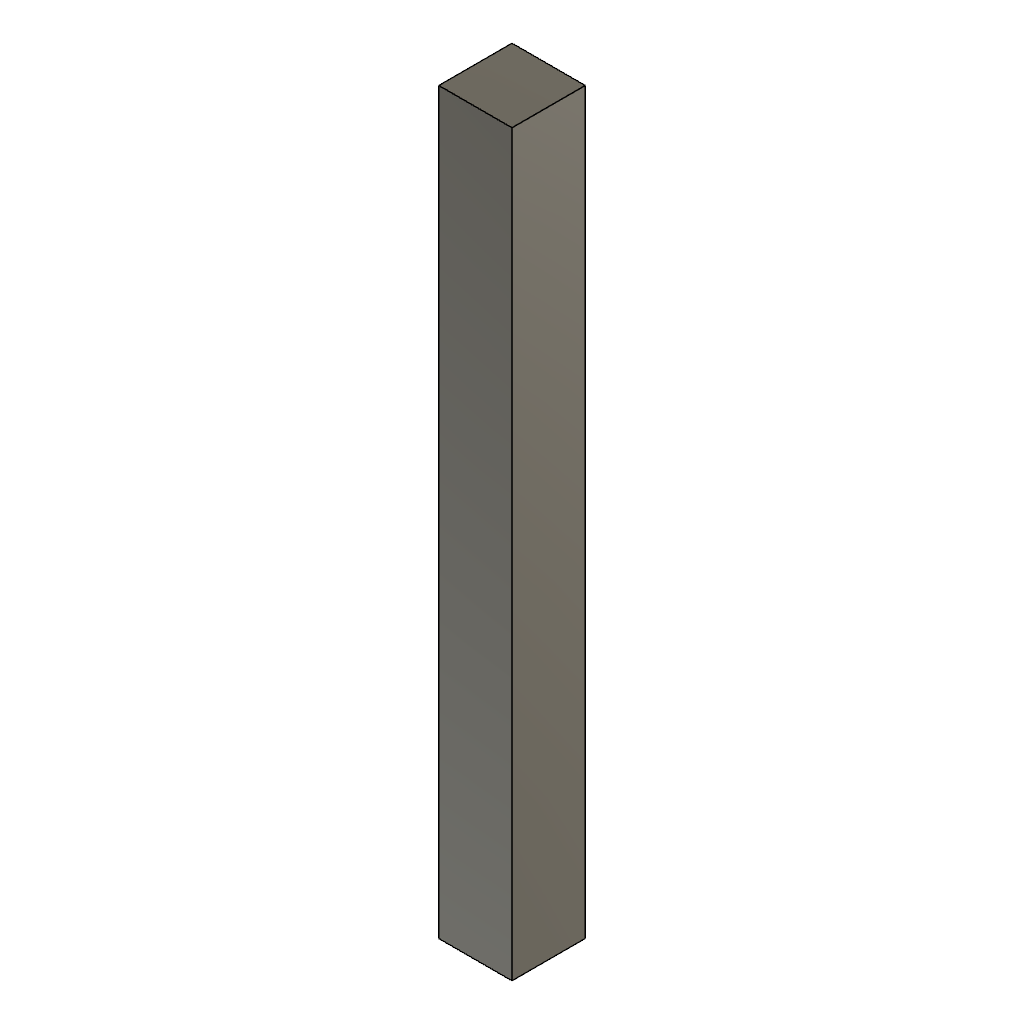
design "pole"
part number: 2026-10-24-16-33-29-752
Autodesk Fusion 360 part; units mm, degrees
sketch "Sketch1" plane through (0, 0, 0) normal (0, 0, 1) x (1, 0, 0)
  line L0 (0, 0) -> (25, 0)
  line L1 (25, 0) -> (25, 25)
  line L2 (25, 25) -> (0, 25)
  line L3 (0, 25) -> (0, 0)
  dimension "d1" = 25
  dimension "d2" = 25
  constraint horizontal L0
  constraint vertical L1
  constraint horizontal L2
  constraint vertical L3
  constraint coincident L0.start L3.end
  measures "d1" distance of L0.start L0.end
  measures "d2" distance of L0.start L2.end
extrude "Extrude1" add sketch "Sketch1" along normal blind 252

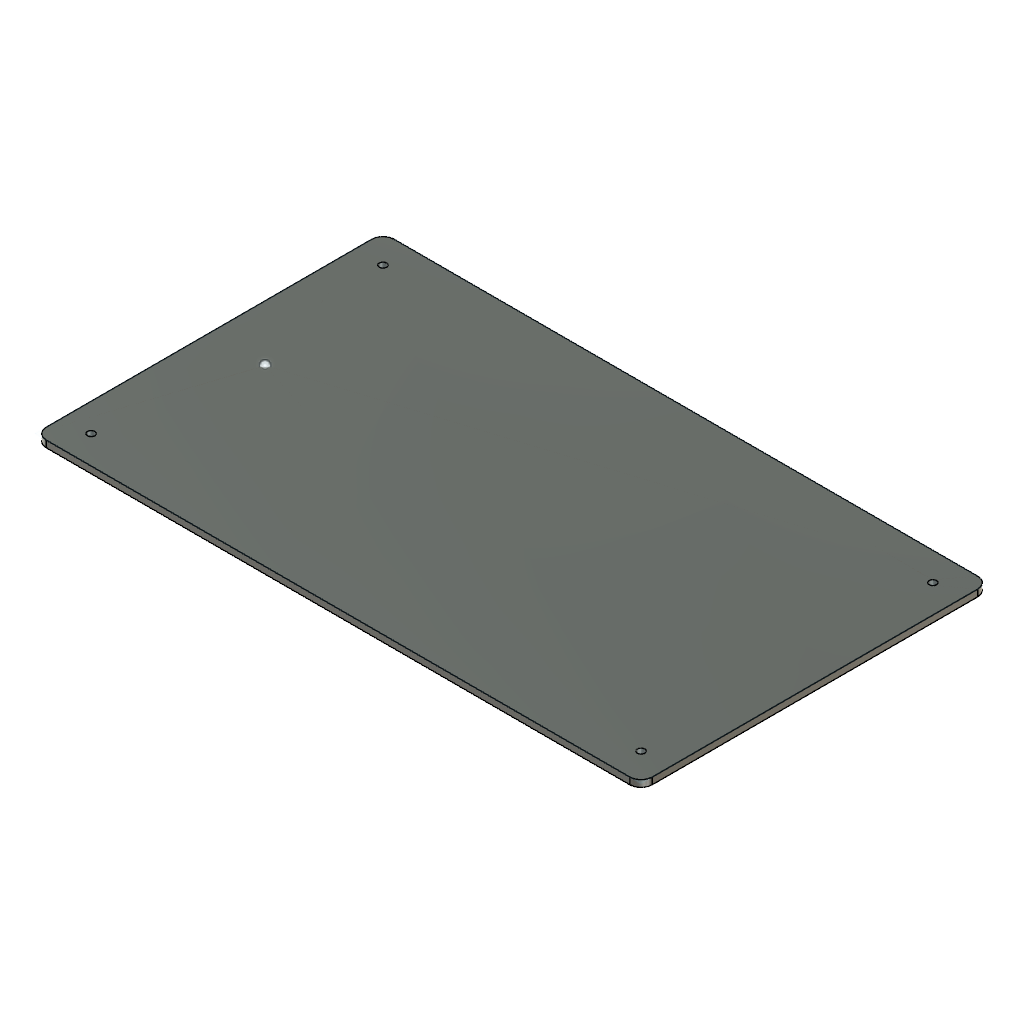
design "base1"
part number: 2026-10-23-09-59-45-106
Autodesk Fusion 360 part; units mm, degrees
sketch "Sketch1" plane through (0, 0, 0) normal (0, 0, 1) x (1, 0, 0)
  line L0 (0, 0) -> (540, 0)
  line L1 (540, 0) -> (540, 310)
  line L2 (540, 310) -> (0, 310)
  line L3 (0, 310) -> (0, 0)
  dimension "d1" = 540
  dimension "d2" = 310
  constraint horizontal L0
  constraint vertical L1
  constraint horizontal L2
  constraint vertical L3
  constraint coincident L0.start L3.end
  measures "d1" distance of L0.start L0.end
  measures "d2" distance of L0.start L2.end
extrude "Extrude1" add sketch "Sketch1" along normal blind 6
sketch "Sketch2" plane through (0, 0, 6) normal (0, 0, 1) x (-1, 0, 0)
  line L0 (0, -310) -> (0, 0)
  line L1 (0, 0) -> (-540, 0)
  line L2 (-540, 0) -> (-540, -310)
  line L3 (-540, -310) -> (0, -310)
  circle A0 centre (-65, -145) radius 3.3
  circle A1 centre (-65, -165) radius 3.3
  circle A2 centre (-165, -165) radius 3.3
  circle A3 centre (-165, -145) radius 3.3
  dimension "d5" = 6.6
  dimension "d6" = 145
  dimension "d7" = 65
  dimension "d8" = 6.6
  dimension "d9" = 6.6
  dimension "d10" = 6.6
  dimension "d11" = 310
  dimension "d12" = 65
  dimension "d13" = 165
  dimension "d14" = 165
  dimension "d15" = 165
  dimension "d16" = 165
  dimension "d17" = 145
  measures "d5" diameter of A0
  measures "d6" distance of L1 A0.centre
  measures "d7" distance of L0 A0.centre
  measures "d8" diameter of A1
  measures "d9" diameter of A2
  measures "d10" diameter of A3
  measures "d11" distance of L0.start L0.end
  measures "d12" distance of L0 A1.centre
  measures "d13" distance of L1 A1.centre
  measures "d14" distance of L0 A3.centre
  measures "d15" distance of L1 A2.centre
  measures "d16" distance of L0 A2.centre
  measures "d17" distance of L1 A3.centre
sketch "Sketch3" plane through (0, 0, 6) normal (0, 0, 1) x (-1, 0, 0)
  line L0 (0, -310) -> (0, 0)
  line L1 (0, 0) -> (-540, 0)
  line L2 (-540, 0) -> (-540, -310)
  line L3 (-540, -310) -> (0, -310)
  circle A0 centre (-50, -155) radius 0.3
  dimension "d36" = 0.6
  dimension "d37" = 155
  dimension "d38" = 50
  measures "d36" diameter of A0
  measures "d37" distance of L1 A0.centre
  measures "d38" distance of L0 A0.centre
fillet "Fillet1" radius 10 4 edges at (0, 310, 3) (540, 310, 3) (540, 0, 3) (0, 0, 3)
sketch "Sketch4" plane through (0, 0, 6) normal (0, 0, 1) x (-1, 0, 0)
  circle A0 centre (-25, -25) radius 3.3
  circle A1 centre (-25, -285) radius 3.3
  circle A2 centre (-515, -25) radius 3.3
  circle A3 centre (-515, -285) radius 3.3
  line L0 (0, 0) -> (-540, 0)
  line L1 (0, -310) -> (0, 0)
  line L2 (-540, 0) -> (-540, -310)
  line L3 (-540, -310) -> (0, -310)
  dimension "d22" = 6.6
  dimension "d23" = 6.6
  dimension "d24" = 6.6
  dimension "d25" = 6.6
  dimension "d26" = 25
  dimension "d27" = 25
  dimension "d28" = 285
  dimension "d29" = 25
  dimension "d30" = 25
  dimension "d31" = 25
  dimension "d32" = 25
  dimension "d33" = 25
  measures "d22" diameter of A0
  measures "d23" diameter of A1
  measures "d24" diameter of A2
  measures "d25" diameter of A3
  measures "d26" distance of A0.centre L0
  measures "d27" distance of A0.centre L1
  measures "d28" distance of A1.centre L0
  measures "d29" distance of A1.centre L1
  measures "d30" distance of A2.centre L2
  measures "d31" distance of A2.centre L0
  measures "d32" distance of A3.centre L3
  measures "d33" distance of A3.centre L2
extrude "Extrude3" cut sketch "Sketch4" against normal through all contours A0 | A1 | A2 | A3
